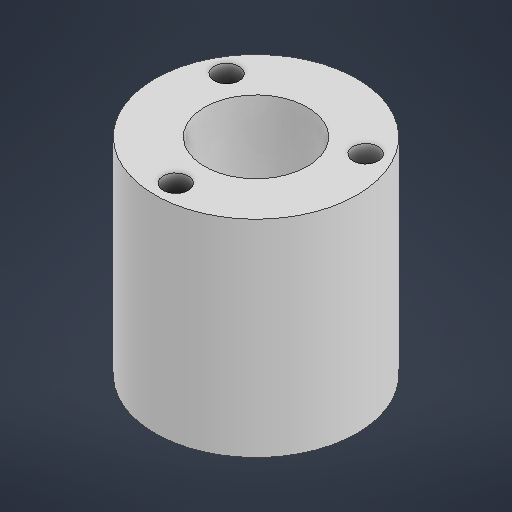
# Autodesk Inventor part: Main_axis
Saved by Autodesk Inventor 2027.1 (Build 311270010, 270A)
## iProperties
Created: 2026-11-02
Part Number: Main_axis
Material: Ogólny
Document SubType Name: Modeling
Designer: User
Density: 1 g/cm^3
Appearance: Domyślna
Author: User
Autodesk Inventor part; units mm, degrees
ref_plane "YZ Plane" through (0, 0, 0) normal (1, 0, 0) x (0, 1, 0)
ref_plane "XZ Plane" through (0, 0, 0) normal (0, 1, 0) x (-1, 0, 0)
ref_plane "XY Plane" through (0, 0, 0) normal (0, 0, 1) x (1, 0, 0)
sketch "Szkic2" plane through (0, 0, 0) normal (0, 1, 0) x (-1, 0, 0)
  circle A0 centre (15.1554, -8.75) radius 2.75
  circle A1 centre (-15.1554, -8.75) radius 2.75
  circle A2 centre (0, 17.5) radius 2.75
  circle A3 centre (15.1554, -8.75) radius 2.75
  circle A4 centre (-15.1554, -8.75) radius 2.75
  circle A5 centre (0, 17.5) radius 2.75
  circle A6 centre (0, 0) radius 22
  circle A7 centre (0, 0) radius 21
  circle A8 centre (0, 0) radius 22
  circle A9 centre (15.1554, -8.75) radius 2.75
  circle A10 centre (15.1554, -8.75) radius 2.75
  circle A11 centre (-15.1554, -8.75) radius 2.75
  circle A12 centre (-15.1554, -8.75) radius 2.75
  circle A13 centre (0, 17.5) radius 2.75
  circle A14 centre (0, 17.5) radius 2.75
  circle A15 centre (0, 17.5) radius 2.75
  circle A16 centre (-15.1554, -8.75) radius 2.75
  circle A17 centre (15.1554, -8.75) radius 2.75
  circle A18 centre (0, 0) radius 22
  circle A19 centre (0, 17.5) radius 2.75
  circle A20 centre (-15.1554, -8.75) radius 2.75
  circle A21 centre (15.1554, -8.75) radius 2.75
  circle A22 centre (0, 0) radius 21
  circle A23 centre (0, 0) radius 22
  circle A24 centre (0, 0) radius 21
  circle A25 centre (0, 0) radius 22
  circle A26 centre (0, 0) radius 22
  circle A27 centre (15.1554, -8.75) radius 2.75
  circle A28 centre (15.1554, -8.75) radius 2.75
  circle A29 centre (-15.1554, -8.75) radius 2.75
  circle A30 centre (-15.1554, -8.75) radius 2.75
  circle A31 centre (0, 17.5) radius 2.75
  circle A32 centre (0, 17.5) radius 2.75
  circle A33 centre (0, 17.5) radius 2.75
  circle A34 centre (-15.1554, -8.75) radius 2.75
  circle A35 centre (15.1554, -8.75) radius 2.75
  circle A36 centre (0, 0) radius 22
  circle A37 centre (0, 17.5) radius 2.75
  circle A38 centre (-15.1554, -8.75) radius 2.75
  circle A39 centre (15.1554, -8.75) radius 2.75
  circle A40 centre (0, 0) radius 21
  circle A41 centre (0, 0) radius 22
  circle A42 centre (0, 0) radius 21
  circle A43 centre (0, 0) radius 22
  circle A44 centre (0, 0) radius 22
  circle A45 centre (0, 0) radius 11.2
  dimension "d18" = 22.4
  constraints: 46 centre point, 1 coincident
  measures "d18" diameter of A45
extrude "Wyciągnięcie proste3" add sketch "Szkic2" along normal blind 11.25 and the other way blind 33.75 contours A6 | A7
equation "\"d19\" = 0.25 * Base_height"
equation "\"d20\" = 0.75 * Base_height"
equation "\"Bearing_ball_radius\" = 2"
equation "\"Base_height\" = 45"
equation "\"Base_wall_thickness\" = 3"
equation "\"Base_floor_thickness\" = 2"
equation "\"Cascet_mounting_holes_size\" = 3"
equation "\"Cascet_mounting_holes_offset\" = 5"
